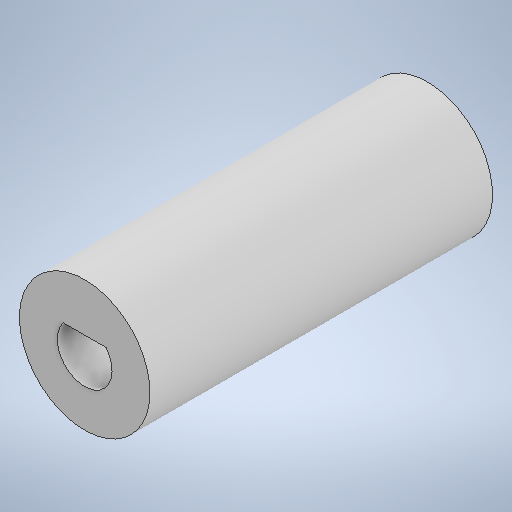
# Autodesk Inventor part: Bucha
Saved by Autodesk Inventor 2025.1 (Build 291241020, 241B)
## iProperties
Created: 2024-11-02
Part Number: Bucha
Material: Genérico
Document SubType Name: Modeling
Designer: Alecs
Density: 1 g/cm^3
Appearance: Padrão
Author: Alecs
Autodesk Inventor part; units mm, degrees
ref_plane "YZ Plane" through (0, 0, 0) normal (1, 0, 0) x (0, 1, 0)
ref_plane "XZ Plane" through (0, 0, 0) normal (0, 1, 0) x (-1, 0, 0)
ref_plane "XY Plane" through (0, 0, 0) normal (0, 0, 1) x (1, 0, 0)
sketch "Esboço1" plane through (0, 0, 0) normal (0, 0, 1) x (1, 0, 0)
  circle A0 centre (0, 0) radius 9.52
  dimension "d0" = 19.04
  constraints: 1 centre point, 1 coincident
  measures "d0" diameter of A0
extrude "Extrusão1" add sketch "Esboço1" along normal mid plane 50
sketch "Esboço2" plane through (0, 0, 25) normal (0, 0, 1) x (1, 0, 0)
  arc A0 (-3.1225, 2.5) -> (3.1225, 2.5) centre (0, 0) ccw
  line L0 (-3.1225, 2.5) -> (3.1225, 2.5)
  point P0 (0, 2.5)
  dimension "d3" = 8
  dimension "d4" = 2.5
  constraints: 2 end point, 2 point on circle, 1 centre point, 1 coincident, 1 horizontal, 1 midpoint
  measures "d3" diameter of A0
  measures "d4" distance of point (0, 2.5) point (0, 0)
extrude "Extrusão2" cut sketch "Esboço2" against normal blind 12
sketch "Esboço4" plane through (0, 0, -25) normal (0, 0, -1) x (-1, 0, 0)
  point P0 (0, 0)
  point P1 (0, 0)
  constraints: 1 coincident
hole "Furo1" at (0, 0, -25) direction (0, 0, 1) diameter 6.647 depth 20 tip angle 118 thread size "M8x1.25" class "6H" standard "ISO Metric profile"
